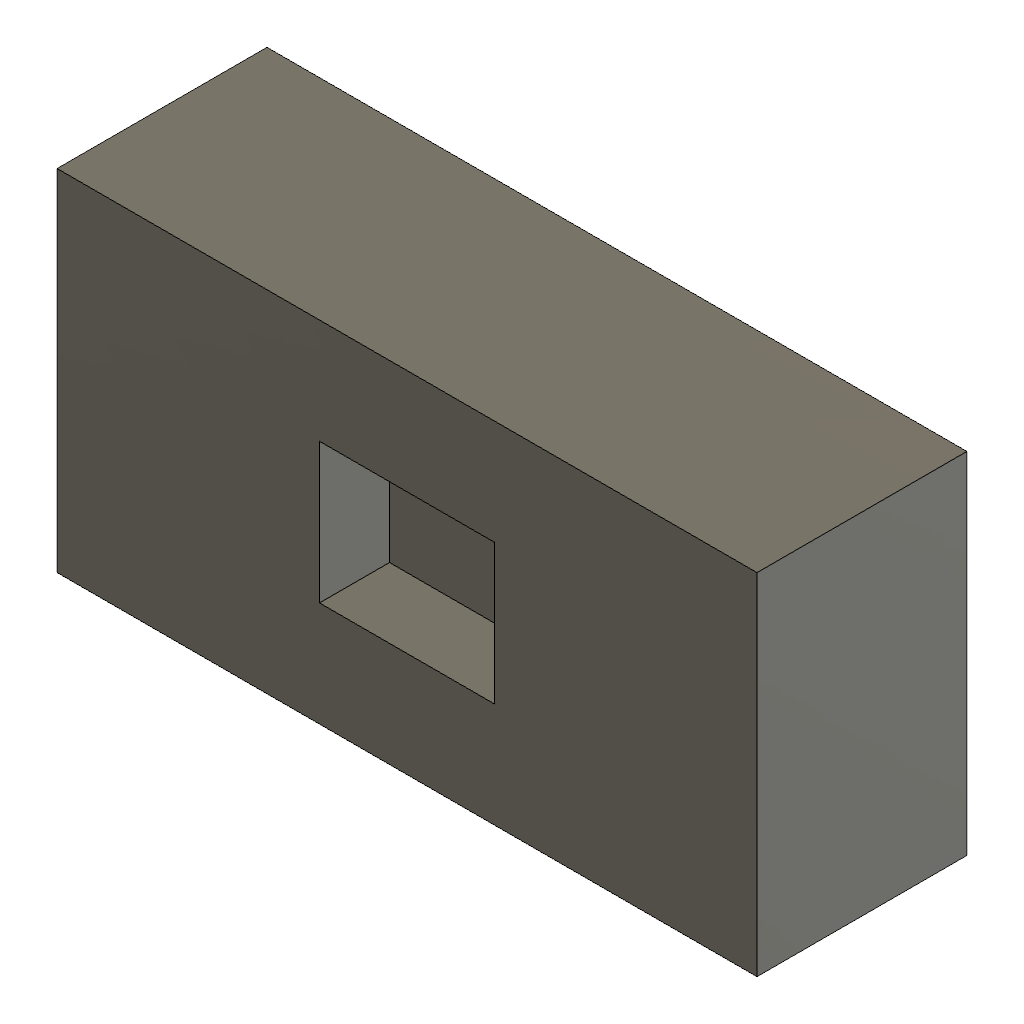
P04-fusion-edit-depth_mm-12 (Autodesk Fusion 360 design; units mm, degrees)
part number: 2026-11-14-20-03-19-192
Autodesk Fusion 360 part; units mm, degrees
sketch "RectangleSketch" plane through (0, 0, 0) normal (0, 0, 1) x (1, 0, 0)
  line L0 (0, 0) -> (40, 0)
  line L1 (40, 0) -> (40, 20)
  line L2 (40, 20) -> (0, 20)
  line L3 (0, 20) -> (0, 0)
  dimension "width_mm" = 40
  dimension "height_mm" = 20
  constraint horizontal L0
  constraint vertical L1
  constraint horizontal L2
  constraint vertical L3
  constraint coincident L0.start L3.end
  measures "width_mm" horizontal distance of L0.start L0.end
  measures "height_mm" vertical distance of L0.start L2.end
extrude "BlindBoss" add sketch "RectangleSketch" along normal blind 12
sketch "CutSketch" plane through (0, 0, 12) normal (0, 0, 1) x (1, 0, 0)
  line L0 (0, 20) -> (0, 0)
  line L1 (0, 0) -> (40, 0)
  line L2 (40, 0) -> (40, 20)
  line L3 (40, 20) -> (0, 20)
  line L4 (15, 6) -> (25, 6)
  line L5 (25, 6) -> (25, 14)
  line L6 (25, 14) -> (15, 14)
  line L7 (15, 14) -> (15, 6)
  line L8 (15, 6) -> (25, 14) construction
  point P0 (20, 10)
  dimension "cut_width_mm" = 10
  dimension "cut_height_mm" = 8
  dimension "cut_center_u_mm" = 20
  dimension "cut_center_v_mm" = 10
  constraint horizontal L4
  constraint vertical L5
  constraint horizontal L6
  constraint vertical L7
  constraint midpoint L8 P0
  measures "cut_width_mm" horizontal distance of L4.start L4.end
  measures "cut_height_mm" vertical distance of L4.start L6.end
  measures "cut_center_u_mm" horizontal distance of P0 L0.end
  measures "cut_center_v_mm" vertical distance of P0 L0.end
extrude "BlindCut" cut sketch "CutSketch" against normal blind 4 contours L4 L5 L6 L7
equation "depth_mm = 12 mm"
equation "cut_center_u_mm = width_mm / 2"
equation "cut_center_v_mm = height_mm / 2"
equation "cut_depth_mm = -( 4 mm )"
